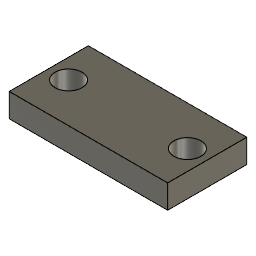
Power button mount (Autodesk Fusion 360 design; units mm, degrees)
Autodesk Fusion 360 part; units mm, degrees
sketch "Sketch1" plane through (0, 0, 0) normal (0, 0, 1) x (1, 0, 0)
  line L0 (0, 0) -> (20, 0)
  line L1 (20, 0) -> (20, 10)
  line L2 (20, 10) -> (0, 10)
  line L3 (0, 10) -> (0, 0)
  dimension "d1" = 20
  dimension "d2" = 10
  constraint horizontal L0
  constraint vertical L1
  constraint horizontal L2
  constraint vertical L3
  constraint coincident L0.start L3.end
  measures "d1" distance of L0.start L0.end
  measures "d2" distance of L0.start L2.end
extrude "Extrude1" add sketch "Sketch1" along normal blind 3
sketch "Sketch2" plane through (0, 0, 3) normal (0, 0, 1) x (-1, 0, 0)
  line L0 (0, -10) -> (0, 0)
  line L1 (0, 0) -> (-20, 0)
  line L2 (-20, 0) -> (-20, -10)
  line L3 (-20, -10) -> (0, -10)
  line L4 (-10, -5) -> (-2.5, -5)
  line L5 (-2.5, -5) -> (-17.5, -5)
  circle A0 centre (-2.5, -5) radius 1.7
  circle A1 centre (-17.5, -5) radius 1.7
  dimension "d5" = 3.4
  dimension "d6" = 3.4
  constraint parallel L3 L4
  constraint parallel L4 L5
  constraint coincident L4.end L5.start
  constraint coincident L5.end A1.centre
  measures "d5" diameter of A0
  measures "d6" diameter of A1
extrude "Extrude2" cut sketch "Sketch2" against normal blind 8656436 contours A0 | A1
